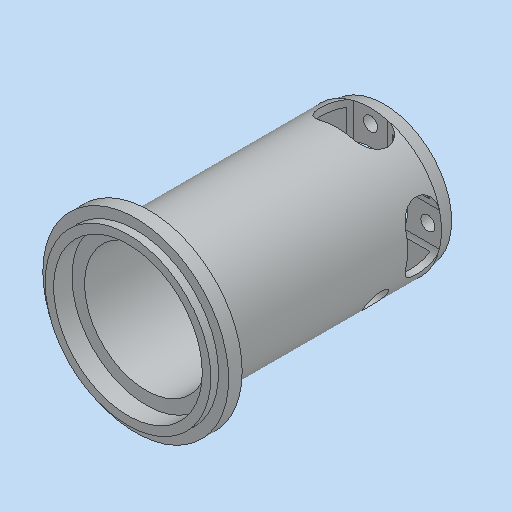
# Autodesk Inventor part: MN0542AN900_G01_101
Saved by Autodesk Inventor 2023.3 (Build 273359000, 359)
## iProperties
Part Number: MN0542AN900_G01_101
Material: 3.3547 AlMg4,5Mn0,7 - AW 5083
Description: =<RBPARTNOTITLE2>
Document SubType Name: Modeling
Designer: Benutzer
Mass: 76.0029 g
Surface Area: 217.4 cm^2
Volume: 28.1492 cm^3
Density: 2.7 g/cm^3
Appearance: Aluminium AnP
RBDOCUMENTTYPE: DRF
RBDOCUMENTVERSION: 00
RBDRAWINGMAINSCALE: 1:1
RBDRAWINGMISSINGSPEC: --
RBDRAWINGVOLUME: --
RBGBEDGESIN1: +0,5
RBGBEDGESIN2: +0,2
RBGBEDGESOUT1: -0,3
RBGBEDGESOUT2: -0,1
RBMATERIAL: =<Material>
RBMATMEETS: --
RBMATNO: =<Part Number>
RBPARTMADEOF: Rd 55 x 75,8 (FM)
RBPARTNO: SIEHE MNR
RBPARTNOTITLE1: manufactured part
RBPARTNOTITLE2: Anfertigungsteil
RBPARTSAFETYINDICATOR: --
RBSURFACE: anodised colourless
RBSURFACE2: eloxiert farblos
RBZEDGESNORM: ISO13715:2002-06
RBZGENDIMCLASS: m
RBZGENDIMNORM: ISO 2768-1:1989-11
RBZGENGEOCLASS: H
RBZGENGEONORM: ISO 2768-2:1989-11
RBZSURFACENORM: ISO13D2:2002-02
RBZTOLERANCENORM: ISO 14405-1:2010-12
AnP_Material: =<Material>
AnP_TemplVers: 20190222
AnP_Kategorie: 1
MaxAbmaße: 55 x 75,8 x 55 (FM)
Author: Benutzer
Keywords: =<RBPARTMADEOF>
Comments: =<RBSURFACE2>
Revision Number: 01
Autodesk Inventor part; units mm, degrees
ref_plane "YZ Plane" through (0, 0, 0) normal (1, 0, 0) x (0, 1, 0)
ref_plane "XZ Plane" through (0, 0, 0) normal (0, 1, 0) x (-1, 0, 0)
ref_plane "XY Plane" through (0, 0, 0) normal (0, 0, 1) x (1, 0, 0)
sketch "Skizze1" plane through (0, 0, 0) normal (0, 0, 1) x (1, 0, 0)
  line L0 (0, 0) -> (0, 75.8)
  line L1 (11, 73.3) -> (13, 73.3)
  line L2 (13, 73.3) -> (13, 75.8)
  line L3 (13, 75.8) -> (20.0027, 75.8)
  line L4 (20.0027, 75.8) -> (21, 71.8)
  line L5 (21, 71.8) -> (21, 8.0417)
  line L6 (21, 8.0417) -> (27.5, 6.3)
  line L7 (27.5, 6.3) -> (27.5, 2.3)
  line L8 (27.5, 2.3) -> (24.5, 2.3)
  line L9 (24.5, 2.3) -> (24.5, 0)
  line L10 (24.5, 0) -> (22, 0)
  line L11 (22, 0) -> (22, 5.4)
  line L12 (22, 5.4) -> (18.25, 5.4)
  line L13 (18.25, 5.4) -> (18.25, 57.8)
  line L14 (18.25, 57.8) -> (19.1, 59.2722)
  line L15 (19.1, 59.2722) -> (19.1, 71.5)
  line L16 (19.1, 71.5) -> (11, 71.5)
  line L17 (11, 71.5) -> (11, 73.3)
  dimension "d0" = 22
  dimension "d1" = 26
  dimension "d2" = 2.3
  dimension "d3" = 4
  dimension "d4" = 73.5
  dimension "d5" = 49
  dimension "d6" = 44
  dimension "d7" = 5.4
  dimension "d8" = 15
  dimension "d9" = 42
  dimension "d10" = 36.5
  dimension "d11" = 38.2
  dimension "d12" = 14
  dimension "d13" = 4
  dimension "d15" = 2.5
  dimension "d17" = 75.8
  dimension "d18" = 71.5
  dimension "d19" = 57.8
  dimension "d20" = 55
  dimension "d40" = 30
  constraints: 36 end point, 10 perpendicular, 3 parallel, 2 point on line, 1 horizontal, 1 vertical
  measures "d0" diameter of L17 L0
  measures "d1" diameter of L2 L0
  measures "d2" distance between parallel lines of L10 L8
  measures "d3" distance of L6.end L7.end
  measures "d4" distance between parallel lines of L3 L8
  measures "d5" diameter of L9 L0
  measures "d6" diameter of L11 L0
  measures "d7" distance of L10.end L11.end
  measures "d8" angle of L6 L8
  measures "d9" diameter of L5 L0
  measures "d10" diameter of L13 L0
  measures "d11" diameter of L15 L0
  measures "d12" angle of L4 L2
  measures "d13" distance from line of L4.end L3
  measures "d15" distance between parallel lines of L1 L3
  measures "d17" distance from line of L9.end L3
  measures "d18" distance between parallel lines of L10 L16
  measures "d19" distance from line of L13.end L10
  measures "d20" diameter of L7 L0
  measures "d40" angle of L14 L13
revolve "Umdrehung1" add sketch "Skizze1" angle 360 about axis through (0, 0, 0) along (0, 1, 0)
sketch "Skizze2" plane through (0, 75.8, 0) normal (0, 1, 0) x (1, 0, 0)
  circle A0 centre (0, 0) radius 17 construction
  point P0 (0, 17)
  point P1 (-17, 0)
  point P2 (0, -17)
  point P3 (17, 0)
  dimension "d22" = 34
  constraints: 4 point on circle, 2 horizontal alignment, 2 vertical alignment, 1 centre point, 1 coincident
  measures "d22" diameter of A0
hole "Bohrung1" at (0, 75.8, -17) at (-17, 75.8, 0) at (0, 75.8, 17) at (17, 75.8, 0) direction (0, -1, 0) diameter 4.2 end up to surface
sketch "Skizze3" plane through (0, 0, 0) normal (1, 0, 0) x (0, 1, 0)
  point P0 (0, 0)
  point P1 (55.8, -11.5)
  dimension "d30" = 11.5
  dimension "d31" = 55.8
  measures "d30" vertical distance of point (55.8, -11.5) point (0, 0)
  measures "d31" horizontal distance of point (55.8, -11.5) point (0, 0)
hole "Bohrung2" at (0, 55.8, -11.5) direction (1, 0, 0) diameter 6.5 end through all
fillet "Rundung1" radius 0.5 1 edges at (-21, 8.0417, 0)
sketch "Skizze4" plane through (0, 0, 0) normal (1, 0, 0) x (0, 1, 0)
  line L0 (66.8, 5) -> (66.8, -5) construction
  line L1 (61.8, 5) -> (61.8, -5)
  line L2 (71.8, -5) -> (71.8, 5)
  arc A0 (71.8, 5) -> (61.8, 5) centre (66.8, 5) ccw
  arc A1 (61.8, -5) -> (71.8, -5) centre (66.8, -5) ccw
  line L3 (-15.16, 0) -> (90.96, 0) projected
  line L4 (75.8, 20.0027) -> (75.8, -20.0027) projected
  point P0 (0, 0)
  point P1 (66.8, 0)
  dimension "d41" = 10
  dimension "d42" = 10
  dimension "d43" = 9
  constraints: 8 end point, 4 point on circle, 4 tangent, 2 centre point, 1 midpoint, 1 parallel, 1 point on line, 1 vertical
  measures "d41" distance between parallel lines of L2 L1
  measures "d42" distance of L0.start L0.end
  measures "d43" distance between parallel lines of L4 L0
extrude "Extrusion1" cut sketch "Skizze4" along normal through all both and the other way through all
sketch "Skizze5" plane through (0, 0, 0) normal (0, 0, 1) x (1, 0, 0)
  line L0 (0, 90.96) -> (0, -15.16) projected
  line L1 (-5, 66.8) -> (5, 66.8) construction
  line L2 (-5, 71.8) -> (5, 71.8)
  line L3 (5, 61.8) -> (-5, 61.8)
  arc A0 (-5, 71.8) -> (-5, 61.8) centre (-5, 66.8) ccw
  arc A1 (5, 61.8) -> (5, 71.8) centre (5, 66.8) ccw
  line L4 (-20.0027, 75.8) -> (20.0027, 75.8) projected
  point P0 (0, 0)
  point P1 (0, 66.8)
  dimension "d46" = 9
  dimension "d47" = 10
  dimension "d48" = 10
  constraints: 8 end point, 4 point on circle, 4 tangent, 2 centre point, 1 horizontal, 1 midpoint, 1 parallel, 1 point on line
  measures "d46" distance between parallel lines of L4 L1
  measures "d47" distance of L1.start L1.end
  measures "d48" distance between parallel lines of L3 L2
extrude "Extrusion2" cut sketch "Skizze5" along normal through all both and the other way through all
